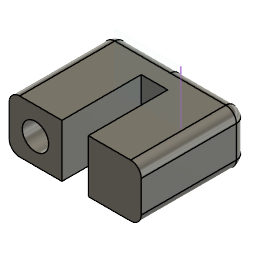
D_suporte_sensor_temperatura (Autodesk Fusion 360 design; units mm, degrees)
Autodesk Fusion 360 part; units mm, degrees
sketch "Esboço1" plane through (0, 0, 0) normal (0, 1, 0) x (1, 0, 0)
  line L0 (-2.5, 0.0206) -> (-12.5, 0.0206)
  line L1 (-12.5, 0.0206) -> (-12.5, 20.0206)
  line L2 (-12.5, 0.0206) -> (-2.5, 0.0206)
  line L3 (-2.5, 0.0206) -> (-2.5, 15.0206)
  line L4 (-12.5, 20.0206) -> (0, 20.0206)
  line L5 (0, 0) -> (0, 20.0206)
  line L6 (-2.5, 15.0206) -> (0, 15.0206)
  line L7 (2.5, 15.0206) -> (0, 15.0206)
  line L8 (12.5, 20.0205) -> (0, 20.0206)
  line L9 (12.5, 0.0205) -> (12.5, 20.0205)
  line L10 (2.5, 0.0206) -> (12.5, 0.0205)
  line L11 (2.5, 0.0206) -> (2.5, 15.0206)
  line L12 (12.5, 0.0205) -> (2.5, 0.0206)
  dimension "d1" = 12.5
  dimension "d2" = 20
  dimension "d3" = 10
  dimension "d4" = 15
  dimension "d5" = 12.5
  constraint horizontal L0
  constraint perpendicular L0 L1
  constraint perpendicular L1 L2
  constraint perpendicular L2 L3
  constraint perpendicular L1 L4
  constraint coincident L5.start origin
  constraint symmetric origin L5 L5.start
  constraint perpendicular L5 L6
  constraint coincident L5 L6.end
  constraint symmetric L0.end L5 L9.start
  constraint symmetric L1.end L5 L8.start
  constraint symmetric L0.start L5 L10.start
  constraint symmetric L3.end L5 L7.start
  constraint symmetric L4.end L5 L8.end
  constraint symmetric L5 origin L5.start
  constraint symmetric L5 L6.end L7.end
  measures "d1" distance of L5.start L0.end
  measures "d2" distance of L0.end L1.end
  measures "d3" distance of L0.end L0.start
  measures "d4" distance of L0.start L3.end
  measures "d5" distance of L1.end L4.end
extrude "Extrusão1" add sketch "Esboço1" along normal blind 10
sketch "Esboço2" plane through (0, 0, -20.0206) normal (0, 0, -1) x (-1, 0, 0)
  line L0 (0, 0) -> (12.5, 0)
  line L1 (12.5, 0) -> (12.5, 10)
  line L2 (12.5, 10) -> (0, 10)
  line L3 (0, 10) -> (0, 0)
fillet "Arredondamento1" radius 2 1 edges at (12.5, 10, -10.0205)
fillet "Arredondamento2" radius 2 1 edges at (-12.5, 5, -20.0206)
fillet "Arredondamento3" radius 2 4 edges at (-5.25, 10, -20.0206) (-11.9142, 10, -19.4348) (-12.5, 10, -9.0206) (6.25, 10, -20.0205)
fillet "Arredondamento4" radius 2 4 edges at (-5.25, 0, -20.0206) (6.25, 0, -20.0205) (-11.9142, 0, -19.4348) (-12.5, 0, -9.0206)
hole "Furo2" at (-7.5, 4.8451, -20.0206) direction (0, 0, 1) diameter 5 depth 20 tip angle 180
